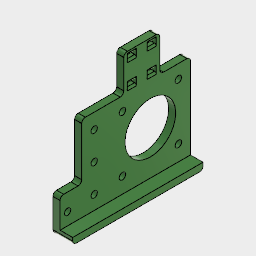
RailCore II 300ZLT (Autodesk Fusion 360 archive; units mm, degrees)
design "Titan_Mount"
Autodesk Fusion 360 part; units mm, degrees
(part 1 of 2)
sketch "sketch 380" plane through (7.7978, 0, 0) normal (-1, 0, 0) x (0, 0, 1)
  circle A0 centre (-23.4476, 32.6221) radius 1.75
  circle A1 centre (8.4572, 79.2609) radius 1.8
  circle A2 centre (-22.5428, 48.2609) radius 1.8
  circle A3 centre (-22.5428, 79.2609) radius 1.8
  circle A4 centre (8.4572, 48.2609) radius 1.8
  circle A5 centre (-7.0428, 63.7609) radius 14
  circle A6 centre (-7.9476, 32.6221) radius 1.75
  circle A7 centre (7.5524, 32.6221) radius 1.75
  line L0 (16, 25.672) -> (-34.9535, 25.672)
  line L1 (16, 86) -> (16, 25.672)
  line L2 (-34.9535, 86) -> (16, 86)
  line L3 (-34.9535, 25.672) -> (-34.9535, 86)
extrude "Extrude1" add sketch "sketch 380" along normal blind 4
sketch "sketch 426" plane through (7.7978, 0, 0) normal (1, 0, 0) x (0, 0, -1)
  line L0 (34.9535, 25.672) -> (34.9535, 86)
  line L1 (34.9535, 25.672) -> (34.9535, 86)
  line L2 (34.9535, 86) -> (31.2032, 86)
  line L3 (34.9535, 86) -> (31.2032, 86)
  line L4 (31.2032, 86) -> (31.2032, 25.672)
  line L5 (31.2032, 25.672) -> (34.9535, 25.672)
  line L6 (31.2032, 25.672) -> (34.9535, 25.672)
extrude "Extrude2" add sketch "sketch 426" along normal blind 7
sketch "Sketch1" plane through (0, 0, 16) normal (0, 0, 1) x (-1, 0, 0)
  line L0 (-7.7978, -25.672) -> (-7.7978, -86)
  line L1 (-3.7978, -86) -> (-3.7978, -25.672)
  line L2 (-3.7978, -69) -> (-7.7982, -69)
  line L3 (-7.7978, -49) -> (-3.7968, -49)
  line L4 (-7.7978, -86) -> (-3.7978, -86)
  line L5 (-3.7978, -25.672) -> (-7.7978, -25.672)
  dimension "d1" = 20
  measures "d1" distance of L2 L3
extrude "Extrude3" add sketch "Sketch1" along normal blind 20 contours L0 L1 L2 L3
sketch "Sketch2" plane through (7.7978, 0, 0) normal (1, 0, 0) x (0, 1, 0)
  line L0 (25.672, 16) -> (25.672, -31.2032)
  line L1 (25.672, -31.2032) -> (86, -31.2032)
  line L2 (86, -31.2032) -> (86, 16)
  line L3 (86, 16) -> (69, 16)
  line L4 (69, 16) -> (69, 36)
  line L5 (69, 36) -> (49, 36)
  line L6 (49, 36) -> (49, 16)
  line L7 (49, 16) -> (25.672, 16)
  circle A0 centre (32.6221, -7.9476) radius 1.75
  circle A1 centre (32.6221, 7.5524) radius 1.75
  circle A2 centre (63.7609, -7.0428) radius 14
  circle A3 centre (48.2609, 8.4572) radius 1.8
  circle A4 centre (79.2609, -22.5428) radius 1.8
  circle A5 centre (48.2609, -22.5428) radius 1.8
  circle A6 centre (79.2609, 8.4572) radius 1.8
  circle A7 centre (32.6221, -23.4476) radius 1.75
  line L8 (67, 34) -> (62, 34)
  line L9 (62, 34) -> (62, 31.5)
  line L10 (62, 31.5) -> (67, 31.5)
  line L11 (67, 31.5) -> (67, 34)
  line L12 (51, 34) -> (56, 34)
  line L13 (56, 34) -> (56, 31.5)
  line L14 (56, 31.5) -> (51, 31.5)
  line L15 (51, 31.5) -> (51, 34)
  line L16 (51, 20.5) -> (56, 20.5)
  line L17 (56, 20.5) -> (56, 18)
  line L18 (56, 18) -> (51, 18)
  line L19 (51, 18) -> (51, 20.5)
  line L20 (62, 20.5) -> (67, 20.5)
  line L21 (67, 20.5) -> (67, 18)
  line L22 (67, 18) -> (62, 18)
  line L23 (62, 18) -> (62, 20.5)
  dimension "d5" = 5
  dimension "d6" = 2.5
  dimension "d7" = 5
  dimension "d8" = 2.5
  dimension "d9" = 2.5
  dimension "d10" = 5
  dimension "d11" = 5
  dimension "d12" = 2.5
  dimension "d13" = 2
  dimension "d14" = 2
  dimension "d15" = 2
  dimension "d16" = 2
  dimension "d17" = 2
  dimension "d18" = 2
  dimension "d19" = 11
  dimension "d20" = 11
  measures "d5" distance of L8.start L8.end
  measures "d6" distance of L8.start L10.end
  measures "d7" distance of L12.start L12.end
  measures "d8" distance of L12.start L14.end
  measures "d9" distance of L16.start L18.end
  measures "d10" distance of L16.start L16.end
  measures "d11" distance of L20.start L20.end
  measures "d12" distance of L20.start L22.end
  measures "d13" distance of L6 L15
  measures "d14" distance of L6 L19
  measures "d15" distance of L4 L21
  measures "d16" distance of L4 L11
  measures "d17" distance of L5 L12
  measures "d18" distance of L5 L8
  measures "d19" distance of L14 L16
  measures "d20" distance of L10 L20
extrude "Extrude4" cut sketch "Sketch2" against normal up to surface (4 mm away) contours L8 L9 L10 L11 | L12 L13 L14 L15 | L16 L17 L18 L19 | L20 L21 L22 L23
fillet "Fillet3" radius 2 4 edges at (5.7978, 49, 16) (5.7978, 49, 36) (5.7978, 69, 16) (5.7978, 69, 36)
fillet "Fillet4" radius 1 16 edges at (3.7978, 64.5, 18) (3.7978, 64.5, 20.5) (3.7978, 64.5, 31.5) (3.7978, 64.5, 34) (3.7978, 53.5, 34) (3.7978, 53.5, 31.5) (3.7978, 53.5, 20.5) (3.7978, 53.5, 18) (7.7978, 64.5, 18) (7.7978, 53.5, 18) (7.7978, 53.5, 20.5) (7.7978, 64.5, 20.5) (7.7978, 64.5, 31.5) (7.7978, 53.5, 31.5) (7.7978, 53.5, 34) (7.7978, 64.5, 34)
sketch "Sketch3" plane through (0, 25.672, 0) normal (0, -1, 0) x (1, 0, 0)
  line L0 (3.7978, 16) -> (3.7978, -34.9535)
  line L1 (3.7978, -34.9535) -> (14.7978, -34.9535)
  line L2 (14.7978, -31.2032) -> (7.7978, -31.2032)
  line L3 (7.7978, -31.2032) -> (7.7978, 16)
  line L4 (7.7978, -14.9535) -> (3.7978, -14.9535)
  line L5 (14.7978, -34.9535) -> (14.7978, -31.2032)
  line L6 (7.7978, 16) -> (3.7978, 16)
  dimension "d25" = 20
  measures "d25" distance of L1 L4
extrude "Extrude5" add sketch "Sketch3" along normal blind 12 contours L0 L1 L2 L3 L4 L5
fillet "Fillet5" radius 2 7 edges at (3.7978, 49.836, -34.9535) (9.2978, 86, -34.9535) (5.7978, 86, 16) (5.7978, 25.672, 16) (5.7978, 25.672, -14.9535) (5.7978, 13.672, -14.9535) (9.2978, 13.672, -34.9535)
sketch "Sketch4" plane through (3.7978, 0, 0) normal (-1, 0, 0) x (0, -1, 0)
  circle A0 centre (-32.6221, -23.4476) radius 1.75
  circle A1 centre (-79.2609, 8.4572) radius 1.8
  circle A2 centre (-48.2609, -22.5428) radius 1.8
  circle A3 centre (-79.2609, -22.5428) radius 1.8
  circle A4 centre (-48.2609, 8.4572) radius 1.8
  circle A5 centre (-63.7609, -7.0428) radius 14
  circle A6 centre (-32.6221, 7.5524) radius 1.75
  circle A7 centre (-32.6221, -7.9476) radius 1.75
  line L0 (-62, 21.5) -> (-62, 17)
  line L1 (-62, 17) -> (-67, 17)
  line L2 (-67, 17) -> (-67, 21.5)
  line L3 (-67, 21.5) -> (-62, 21.5)
  line L4 (-62, 35) -> (-62, 30.5)
  line L5 (-62, 30.5) -> (-67, 30.5)
  line L6 (-67, 30.5) -> (-67, 35)
  line L7 (-67, 35) -> (-62, 35)
  line L8 (-56, 30.5) -> (-56, 35)
  line L9 (-56, 35) -> (-51, 35)
  line L10 (-51, 35) -> (-51, 30.5)
  line L11 (-51, 30.5) -> (-56, 30.5)
  line L12 (-56, 17) -> (-56, 21.5)
  line L13 (-56, 21.5) -> (-51, 21.5)
  line L14 (-51, 21.5) -> (-51, 17)
  line L15 (-51, 17) -> (-56, 17)
  arc A8 (-13.672, -16.9535) -> (-15.672, -14.9535) centre (-15.672, -16.9535) ccw
  line L16 (-15.672, -14.9535) -> (-23.672, -14.9535)
  arc A9 (-25.672, -12.9535) -> (-23.672, -14.9535) centre (-23.672, -12.9535) ccw
  line L17 (-25.672, -12.9535) -> (-25.672, 14)
  arc A10 (-25.672, 14) -> (-27.672, 16) centre (-27.672, 14) ccw
  line L18 (-27.672, 16) -> (-47, 16)
  arc A11 (-49, 18) -> (-47, 16) centre (-47, 18) ccw
  line L19 (-49, 18) -> (-49, 34)
  arc A12 (-49, 34) -> (-51, 36) centre (-51, 34) ccw
  line L20 (-51, 36) -> (-67, 36)
  arc A13 (-67, 36) -> (-69, 34) centre (-67, 34) ccw
  line L21 (-69, 34) -> (-69, 18)
  arc A14 (-71, 16) -> (-69, 18) centre (-71, 18) ccw
  line L22 (-71, 16) -> (-84, 16)
  arc A15 (-84, 16) -> (-86, 14) centre (-84, 14) ccw
  line L23 (-86, 14) -> (-86, -32.9535)
  line L24 (-86, -32.9535) -> (-13.672, -32.9535)
  line L25 (-13.672, -32.9535) -> (-13.672, -16.9535)
  line L26 (-32.6221, -23.4476) -> (-17.8531, -23.4476) construction
  line L27 (-17.8531, -23.4476) -> (-17.8531, -24.4346) construction
  line L28 (-17.8531, -24.4346) -> (-32.6221, -24.4346) construction
  line L29 (-32.6221, -24.4346) -> (-32.6221, -23.4476) construction
  circle A16 centre (-17.8531, -24.4346) radius 1.75
  dimension "d30" = 0.987
  dimension "d31" = 14.769
  dimension "d32" = 3.5
  measures "d30" distance of L26 L28
  measures "d31" distance of L27 L29
  measures "d32" diameter of A16
extrude "Extrude6" cut sketch "Sketch4" against normal up to surface (4 mm away) contours A16

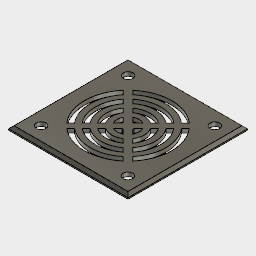
design "Fan_Cover"
Autodesk Fusion 360 part; units mm, degrees
sketch "Sketch1" plane through (0, 0, 0) normal (0, 0, 1) x (1, 0, 0)
  circle A0 centre (1.9885, 1.9886) radius 1.75
  circle A1 centre (2.0234, 33.9886) radius 1.75
  circle A2 centre (34.0234, 33.9537) radius 1.75
  circle A3 centre (33.9885, 1.9537) radius 1.75
  line L0 (-4.0115, 39.9886) -> (39.9885, 39.9886)
  line L1 (39.9885, 39.9886) -> (39.9885, -4.0114)
  line L2 (39.9885, -4.0114) -> (-4.0115, -4.0114)
  line L3 (-4.0115, -4.0114) -> (-4.0115, 39.9886)
  circle A4 centre (18, 18) radius 2
  circle A5 centre (18, 18) radius 4
  circle A6 centre (18, 18) radius 6
  circle A7 centre (18, 18) radius 8
  circle A8 centre (18, 18) radius 10
  circle A9 centre (18, 18) radius 14
  circle A10 centre (18, 18) radius 12
  line L4 (1.9885, 1.9886) -> (34.0234, 33.9537) construction
  line L5 (2.0234, 33.9886) -> (33.9885, 1.9537) construction
  circle A11 centre (18, 18) radius 16
  line L6 (7.6057, 30.1638) -> (30.1411, 7.5792)
  line L7 (5.8378, 28.3962) -> (28.3696, 5.8152)
  line L8 (28.4273, 30.1356) -> (5.8417, 7.5992)
  line L9 (7.6103, 5.8322) -> (30.1904, 28.3632)
  line L10 (-4.0115, 17.9886) -> (39.9885, 17.9886) construction
  line L11 (17.9885, 39.9886) -> (17.9885, -4.0114) construction
  dimension "d1" = 3.5
  dimension "d2" = 3.5
  dimension "d3" = 3.5
  dimension "d4" = 3.5
  dimension "d5" = 32
  dimension "d6" = 32
  dimension "d7" = 32
  dimension "d8" = 32
  dimension "d14" = 6
  dimension "d15" = 6
  dimension "d16" = 6
  dimension "d17" = 6
  dimension "d18" = 4
  dimension "d30" = 8
  dimension "d31" = 12
  dimension "d32" = 16
  dimension "d33" = 20
  dimension "d34" = 28
  dimension "d35" = 24
  dimension "d41" = 32
  dimension "d42" = 1.25
  dimension "d43" = 1.25
  dimension "d44" = 1.25
  dimension "d45" = 1.25
  measures "d1" diameter of A0
  measures "d2" diameter of A1
  measures "d3" diameter of A2
  measures "d4" diameter of A3
  measures "d5" distance of A0.centre A3.centre
  measures "d6" distance of A0.centre A1.centre
  measures "d7" distance of A1.centre A2.centre
  measures "d8" distance of A2.centre A3.centre
  measures "d14" distance of A0.centre L3
  measures "d15" distance of A3.centre L1
  measures "d16" distance of A1.centre L0
  measures "d17" distance of A0.centre L2
  measures "d18" diameter of A4
  measures "d30" diameter of A5
  measures "d31" diameter of A6
  measures "d32" diameter of A7
  measures "d33" diameter of A8
  measures "d34" diameter of A9
  measures "d35" diameter of A10
  measures "d41" diameter of A11
  measures "d42" distance of L5 L7
  measures "d43" distance of L5 L6
  measures "d44" distance of L4 L8
  measures "d45" distance of L4 L9
extrude "Extrude1" add sketch "Sketch1" along normal blind 1.5 contours L0 L1 L2 L3 | A4 L6 L9 | A4 L6 L8 L9 | A4 A5 L8 L9 | A4 A5 L6 L7 | A4 L6 L7 L9 | A4 L6 L8 | L6 L7 L8 L9 | A5 A6 L6 L9 | A5 A6 L8 L9 | A4 L7 L9 | A5 A6 L6 L7 | A4 L6 L7 L8 | A4 A5 L6 L7 | A5 A6 L6 L8 | A4 L7 L8 L9 | A6 A7 L8 L9 | A4 A5 L8 L9 | A5 A6 L7 L9 | A6 A7 L6 L7 | A4 L7 L8 | A5 A6 L6 L7 | A7 A8 L6 L9 | A7 A8 L8 L9 | A5 A6 L8 L9 | A7 A8 L6 L7 | A5 A6 L7 L8 | A6 A7 L6 L7 | A7 A8 L6 L8 | A8 A10 L8 L9 | A6 A7 L8 L9 | A7 A8 L7 L9 | A8 A10 L6 L7 | A7 A8 L6 L7 | A9 A10 L6 L9 | A9 A10 L8 L9 | A7 A8 L8 L9 | A9 A10 L6 L7 | A7 A8 L7 L8 | A8 A10 L6 L7 | A9 A10 L6 L8 | A9 A11 L8 L9 | A8 A10 L8 L9 | A9 A10 L7 L9 | A9 A11 L6 L7 | A9 A10 L6 L7 | A9 A10 L8 L9 | A9 A10 L7 L8 | A9 A11 L6 L7 | A9 A11 L8 L9
chamfer "Chamfer1" distance 1 angle 45 4 edges at (17.9885, -4.0114, 1.5) (39.9885, 17.9886, 1.5) (-4.0115, 17.9886, 1.5) (17.9885, 39.9886, 1.5)

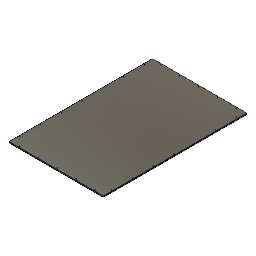
design "300ZLT Back Panel"
Autodesk Fusion 360 part; units mm, degrees
sketch "Sketch1" plane through (0, 0, 0) normal (0, 0, 1) x (1, 0, 0)
  line L0 (0, 0) -> (490, 0)
  line L1 (490, 0) -> (490, -745)
  line L2 (490, -745) -> (0, -745)
  line L3 (0, -745) -> (0, 0)
  line L4 (7.5, -7.5) -> (482.5, -7.5) construction
  line L5 (482.5, -7.5) -> (482.5, -737.5) construction
  line L6 (482.5, -737.5) -> (7.5, -737.5) construction
  line L7 (7.5, -737.5) -> (7.5, -7.5) construction
  line L8 (0, -50) -> (490, -50) construction
  line L9 (0, -695) -> (490, -695) construction
  line L10 (0, -157.5) -> (490, -157.5) construction
  line L11 (0, -265) -> (490, -265) construction
  line L12 (0, -372.5) -> (490, -372.5) construction
  line L13 (50, 0) -> (50, -745) construction
  line L14 (440, 0) -> (440, -745) construction
  line L15 (147.5, 0) -> (147.5, -745) construction
  line L16 (245, 0) -> (245, -745) construction
  line L17 (342.5, 0) -> (342.5, -745) construction
  circle A0 centre (50, -737.5) radius 1.75
  circle A1 centre (147.5, -737.5) radius 1.75
  circle A2 centre (245, -737.5) radius 1.75
  circle A3 centre (342.5, -737.5) radius 1.75
  circle A4 centre (440, -737.5) radius 1.75
  circle A5 centre (7.5, -695) radius 1.75
  circle A6 centre (7.5, -372.5) radius 1.75
  circle A7 centre (7.5, -372.5) radius 1.75
  circle A8 centre (7.5, -157.5) radius 1.75
  circle A9 centre (7.5, -50) radius 1.75
  circle A10 centre (50, -7.5) radius 1.75
  circle A11 centre (147.5, -7.5) radius 1.75
  circle A12 centre (245, -7.5) radius 1.75
  circle A13 centre (342.5, -7.5) radius 1.75
  circle A14 centre (440, -7.5) radius 1.75
  circle A15 centre (482.5, -50) radius 1.75
  circle A16 centre (482.5, -157.5) radius 1.75
  circle A17 centre (482.5, -372.5) radius 1.75
  circle A18 centre (482.5, -372.5) radius 1.75
  circle A19 centre (482.5, -695) radius 1.75
  line L18 (0, -480) -> (490, -480) construction
  line L19 (0, -587.5) -> (490, -587.5) construction
  circle A20 centre (7.5, -480) radius 1.75
  circle A21 centre (7.5, -587.5) radius 1.75
  circle A22 centre (482.5, -480) radius 1.75
  circle A23 centre (482.5, -587.5) radius 1.75
  dimension "d1" = 745
  dimension "d2" = 490
  dimension "d3" = 7.5
  dimension "d4" = 7.5
  dimension "d5" = 7.5
  dimension "d6" = 7.5
  dimension "d9" = 50
  dimension "d10" = 50
  dimension "d11" = 107.5
  dimension "d12" = 107.5
  dimension "d13" = 107.5
  dimension "d14" = 50
  dimension "d15" = 50
  dimension "d16" = 97.5
  dimension "d17" = 97.5
  dimension "d18" = 97.5
  dimension "d20" = 3.5
  dimension "d21" = 3.5
  dimension "d22" = 3.5
  dimension "d23" = 3.5
  dimension "d24" = 3.5
  dimension "d25" = 3.5
  dimension "d26" = 3.5
  dimension "d27" = 3.5
  dimension "d28" = 3.5
  dimension "d29" = 3.5
  dimension "d30" = 3.5
  dimension "d31" = 3.5
  dimension "d32" = 3.5
  dimension "d33" = 3.5
  dimension "d34" = 3.5
  dimension "d35" = 3.5
  dimension "d36" = 3.5
  dimension "d37" = 3.5
  dimension "d38" = 3.5
  dimension "d39" = 3.5
  dimension "d50" = 107.5
  dimension "d51" = 107.5
  dimension "d52" = 3.5
  dimension "d53" = 3.5
  dimension "d54" = 3.5
  dimension "d55" = 3.5
  measures "d1" distance of L0.start L2.end
  measures "d2" distance of L0.start L0.end
  measures "d3" distance of L3 L7
  measures "d4" distance of L2 L6
  measures "d5" distance of L0 L4
  measures "d6" distance of L1 L5
  measures "d9" distance of L0 L8
  measures "d10" distance of L2 L9
  measures "d11" distance of L8 L10
  measures "d12" distance of L10 L11
  measures "d13" distance of L11 L12
  measures "d14" distance of L3 L13
  measures "d15" distance of L1 L14
  measures "d16" distance of L13 L15
  measures "d17" distance of L15 L16
  measures "d18" distance of L16 L17
  measures "d20" diameter of A0
  measures "d21" diameter of A1
  measures "d22" diameter of A2
  measures "d23" diameter of A3
  measures "d24" diameter of A4
  measures "d25" diameter of A5
  measures "d26" diameter of A6
  measures "d27" diameter of A7
  measures "d28" diameter of A8
  measures "d29" diameter of A9
  measures "d30" diameter of A10
  measures "d31" diameter of A11
  measures "d32" diameter of A12
  measures "d33" diameter of A13
  measures "d34" diameter of A14
  measures "d35" diameter of A15
  measures "d36" diameter of A16
  measures "d37" diameter of A17
  measures "d38" diameter of A18
  measures "d39" diameter of A19
  measures "d50" distance of L12 L18
  measures "d51" distance of L18 L19
  measures "d52" diameter of A20
  measures "d53" diameter of A21
  measures "d54" diameter of A22
  measures "d55" diameter of A23
extrude "Extrude1" add sketch "Sketch1" along normal blind 6.35
fillet "Fillet1" radius 5 4 edges at (490, -745, 3.175) (0, -745, 3.175) (0, 0, 3.175) (490, 0, 3.175)
equation "d1 = YDepth"
equation "d2 = XWidth"
equation "d3 = HoleOffset"
equation "d4 = HoleOffset"
equation "d5 = HoleOffset"
equation "d6 = HoleOffset"
equation "HoleOffset = 7.5 mm"
equation "Diameter = 3.5 mm"
equation "d9 = EdgeToFirstHole"
equation "d10 = EdgeToFirstHole"
equation "d11 = YSpacing"
equation "d12 = YSpacing"
equation "d13 = YSpacing"
equation "d14 = EdgeToFirstHole"
equation "d15 = EdgeToFirstHole"
equation "d16 = XSpacing"
equation "d17 = XSpacing"
equation "d18 = XSpacing"
equation "d20 = Diameter"
equation "d21 = Diameter"
equation "d22 = Diameter"
equation "d23 = Diameter"
equation "d24 = Diameter"
equation "d25 = Diameter"
equation "d26 = Diameter"
equation "d27 = Diameter"
equation "d28 = Diameter"
equation "d29 = Diameter"
equation "d30 = Diameter"
equation "d31 = Diameter"
equation "d32 = Diameter"
equation "d33 = Diameter"
equation "d34 = Diameter"
equation "d35 = Diameter"
equation "d36 = Diameter"
equation "d37 = Diameter"
equation "d38 = Diameter"
equation "d39 = Diameter"
equation "EdgeToFirstHole = 50 mm"
equation "YDepth = 745 mm"
equation "XWidth = 490 mm"
equation "YSpacing = ( YDepth - ( 2 * EdgeToFirstHole ) ) / 6"
equation "XSpacing = ( XWidth - ( 2 * EdgeToFirstHole ) ) / 4"
equation "thickness = 0.25 in"
equation "d47 = thickness"
equation "d50 = YSpacing"
equation "d51 = YSpacing"
equation "d52 = Diameter"
equation "d53 = Diameter"
equation "d54 = Diameter"
equation "d55 = Diameter"

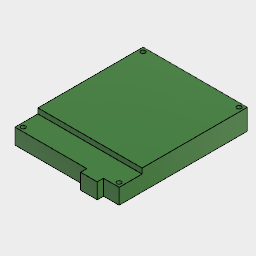
design "DuetWifi v2"
Autodesk Fusion 360 part; units mm, degrees
sketch "Sketch1" plane through (0, 0, 0) normal (0, 0, 1) x (1, 0, 0)
  line L0 (0, 0) -> (100, 0)
  line L1 (100, 0) -> (100, -123)
  line L2 (100, -123) -> (0, -123)
  line L3 (0, -123) -> (0, 0)
  line L4 (85, -123) -> (69, -123)
  line L5 (69, -123) -> (69, -129)
  line L6 (69, -129) -> (85, -129)
  line L7 (85, -129) -> (85, -123)
  circle A0 centre (4, -119) radius 2.1
  circle A1 centre (96, -119) radius 2.1
  circle A2 centre (4, -4) radius 2.1
  circle A3 centre (96, -4) radius 2.1
  line L8 (0, -101) -> (100, -101)
  dimension "d1" = 100
  dimension "d2" = 123
  dimension "d3" = 16
  dimension "d4" = 6
  dimension "d5" = 15
  dimension "d6" = 4.2
  dimension "d7" = 4.2
  dimension "d8" = 4.2
  dimension "d9" = 4.2
  dimension "d10" = 4
  dimension "d11" = 4
  dimension "d12" = 4
  dimension "d13" = 4
  dimension "d14" = 4
  dimension "d15" = 4
  dimension "d16" = 4
  dimension "d17" = 4
  dimension "d18" = 22
  measures "d1" distance of L0.start L0.end
  measures "d2" distance of L0.start L2.end
  measures "d3" distance of L4.start L4.end
  measures "d4" distance of L4.start L6.end
  measures "d5" distance of L1 L7
  measures "d6" diameter of A0
  measures "d7" diameter of A1
  measures "d8" diameter of A2
  measures "d9" diameter of A3
  measures "d10" distance of L3 A2.centre
  measures "d11" distance of L0 A2.centre
  measures "d12" distance of L0 A3.centre
  measures "d13" distance of L1 A3.centre
  measures "d14" distance of L2 A0.centre
  measures "d15" distance of L3 A0.centre
  measures "d16" distance of L2 A1.centre
  measures "d17" distance of L1 A1.centre
  measures "d18" distance of L2 L8
extrude "Extrude1" add sketch "Sketch1" along normal blind 15 contours L1 L2 L3 L4 L8 | L2 L4 L5 L6 L7
extrude "Extrude2" add sketch "Sketch1" along normal blind 20 contours L0 L1 L3 L8

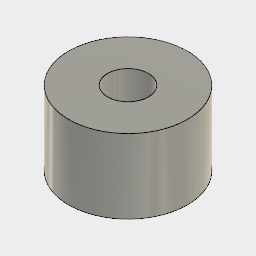
design "Idler_Spacer"
Autodesk Fusion 360 part; units mm, degrees
sketch "Sketch1" plane through (0, 0, 0) normal (0, 0, 1) x (1, 0, 0)
  circle A0 centre (0, 0) radius 2.75
  circle A1 centre (0, 0) radius 8
  dimension "d1" = 5.5
  measures "d1" diameter of A0
extrude "Extrude1" add sketch "Sketch1" along normal blind 10

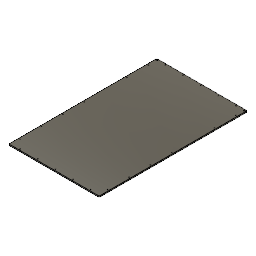
design "300ZLT Left_Panel"
Autodesk Fusion 360 part; units mm, degrees
sketch "Sketch1" plane through (0, 0, 0) normal (0, 0, 1) x (1, 0, 0)
  line L0 (0, 0) -> (455, 0)
  line L1 (455, 0) -> (455, -745)
  line L2 (455, -745) -> (0, -745)
  line L3 (0, -745) -> (0, 0)
  line L4 (7.5, -7.5) -> (447.5, -7.5) construction
  line L5 (447.5, -7.5) -> (447.5, -737.5) construction
  line L6 (447.5, -737.5) -> (7.5, -737.5) construction
  line L7 (7.5, -737.5) -> (7.5, -7.5) construction
  line L8 (0, -50) -> (455, -50) construction
  line L9 (0, -695) -> (455, -695) construction
  line L10 (0, -157.5) -> (455, -157.5) construction
  line L11 (0, -265) -> (455, -265) construction
  line L12 (0, -372.5) -> (455, -372.5) construction
  line L13 (50, 0) -> (50, -745) construction
  line L14 (405, 0) -> (405, -745) construction
  line L15 (138.75, 0) -> (138.75, -745) construction
  line L16 (227.5, 0) -> (227.5, -745) construction
  line L17 (316.25, 0) -> (316.25, -745) construction
  circle A0 centre (50, -737.5) radius 1.75
  circle A1 centre (138.75, -737.5) radius 1.75
  circle A2 centre (227.5, -737.5) radius 1.75
  circle A3 centre (316.25, -737.5) radius 1.75
  circle A4 centre (405, -737.5) radius 1.75
  circle A5 centre (7.5, -695) radius 1.75
  circle A6 centre (7.5, -372.5) radius 1.75
  circle A7 centre (7.5, -372.5) radius 1.75
  circle A8 centre (7.5, -157.5) radius 1.75
  circle A9 centre (7.5, -50) radius 1.75
  circle A10 centre (50, -7.5) radius 1.75
  circle A11 centre (138.75, -7.5) radius 1.75
  circle A12 centre (227.5, -7.5) radius 1.75
  circle A13 centre (316.25, -7.5) radius 1.75
  circle A14 centre (405, -7.5) radius 1.75
  circle A15 centre (447.5, -50) radius 1.75
  circle A16 centre (447.5, -157.5) radius 1.75
  circle A17 centre (447.5, -372.5) radius 1.75
  circle A18 centre (447.5, -372.5) radius 1.75
  circle A19 centre (447.5, -695) radius 1.75
  line L18 (0, -480) -> (455, -480) construction
  line L19 (0, -587.5) -> (455, -587.5) construction
  circle A20 centre (7.5, -480) radius 1.75
  circle A21 centre (7.5, -587.5) radius 1.75
  circle A22 centre (447.5, -587.5) radius 1.75
  circle A23 centre (447.5, -480) radius 1.75
  circle A24 centre (447.5, -7.5) radius 3.5
  circle A25 centre (7.5, -7.5) radius 3.5
  dimension "d1" = 745
  dimension "d2" = 455
  dimension "d3" = 7.5
  dimension "d4" = 7.5
  dimension "d5" = 7.5
  dimension "d6" = 7.5
  dimension "d9" = 50
  dimension "d10" = 50
  dimension "d11" = 107.5
  dimension "d12" = 107.5
  dimension "d13" = 107.5
  dimension "d14" = 50
  dimension "d15" = 50
  dimension "d16" = 88.75
  dimension "d17" = 88.75
  dimension "d18" = 88.75
  dimension "d20" = 3.5
  dimension "d21" = 3.5
  dimension "d22" = 3.5
  dimension "d23" = 3.5
  dimension "d24" = 3.5
  dimension "d25" = 3.5
  dimension "d26" = 3.5
  dimension "d27" = 3.5
  dimension "d28" = 3.5
  dimension "d29" = 3.5
  dimension "d30" = 3.5
  dimension "d31" = 3.5
  dimension "d32" = 3.5
  dimension "d33" = 3.5
  dimension "d34" = 3.5
  dimension "d35" = 3.5
  dimension "d36" = 3.5
  dimension "d37" = 3.5
  dimension "d38" = 3.5
  dimension "d39" = 3.5
  dimension "d58" = 107.5
  dimension "d59" = 107.5
  dimension "d60" = 3.5
  dimension "d61" = 3.5
  dimension "d62" = 3.5
  dimension "d63" = 3.5
  dimension "d64" = 7
  dimension "d65" = 7
  measures "d1" distance of L0.start L2.end
  measures "d2" distance of L0.start L0.end
  measures "d3" distance of L3 L7
  measures "d4" distance of L2 L6
  measures "d5" distance of L0 L4
  measures "d6" distance of L1 L5
  measures "d9" distance of L0 L8
  measures "d10" distance of L2 L9
  measures "d11" distance of L8 L10
  measures "d12" distance of L10 L11
  measures "d13" distance of L11 L12
  measures "d14" distance of L3 L13
  measures "d15" distance of L1 L14
  measures "d16" distance of L13 L15
  measures "d17" distance of L15 L16
  measures "d18" distance of L16 L17
  measures "d20" diameter of A0
  measures "d21" diameter of A1
  measures "d22" diameter of A2
  measures "d23" diameter of A3
  measures "d24" diameter of A4
  measures "d25" diameter of A5
  measures "d26" diameter of A6
  measures "d27" diameter of A7
  measures "d28" diameter of A8
  measures "d29" diameter of A9
  measures "d30" diameter of A10
  measures "d31" diameter of A11
  measures "d32" diameter of A12
  measures "d33" diameter of A13
  measures "d34" diameter of A14
  measures "d35" diameter of A15
  measures "d36" diameter of A16
  measures "d37" diameter of A17
  measures "d38" diameter of A18
  measures "d39" diameter of A19
  measures "d58" distance of L12 L18
  measures "d59" distance of L18 L19
  measures "d60" diameter of A20
  measures "d61" diameter of A21
  measures "d62" diameter of A22
  measures "d63" diameter of A23
  measures "d64" diameter of A24
  measures "d65" diameter of A25
extrude "Extrude1" add sketch "Sketch1" along normal blind 6.35
fillet "Fillet1" radius 5 4 edges at (455, -745, 3.175) (0, -745, 3.175) (0, 0, 3.175) (455, 0, 3.175)
equation "d1 = YDepth"
equation "d2 = XWidth"
equation "d3 = HoleOffset"
equation "d4 = HoleOffset"
equation "d5 = HoleOffset"
equation "d6 = HoleOffset"
equation "HoleOffset = 7.5 mm"
equation "Diameter = 3.5 mm"
equation "d9 = EdgeToFirstHole"
equation "d10 = EdgeToFirstHole"
equation "d11 = YSpacing"
equation "d12 = YSpacing"
equation "d13 = YSpacing"
equation "d14 = EdgeToFirstHole"
equation "d15 = EdgeToFirstHole"
equation "d16 = XSpacing"
equation "d17 = XSpacing"
equation "d18 = XSpacing"
equation "d20 = Diameter"
equation "d21 = Diameter"
equation "d22 = Diameter"
equation "d23 = Diameter"
equation "d24 = Diameter"
equation "d25 = Diameter"
equation "d26 = Diameter"
equation "d27 = Diameter"
equation "d28 = Diameter"
equation "d29 = Diameter"
equation "d30 = Diameter"
equation "d31 = Diameter"
equation "d32 = Diameter"
equation "d33 = Diameter"
equation "d34 = Diameter"
equation "d35 = Diameter"
equation "d36 = Diameter"
equation "d37 = Diameter"
equation "d38 = Diameter"
equation "d39 = Diameter"
equation "EdgeToFirstHole = 50 mm"
equation "YDepth = 745 mm"
equation "XWidth = 455 mm"
equation "YSpacing = ( YDepth - ( 2 * EdgeToFirstHole ) ) / 6"
equation "XSpacing = ( XWidth - ( 2 * EdgeToFirstHole ) ) / 4"
equation "thickness = 0.25 in"
equation "d47 = thickness"
equation "d58 = YSpacing"
equation "d59 = YSpacing"
equation "d60 = Diameter"
equation "d61 = Diameter"
equation "d62 = Diameter"
equation "d63 = Diameter"

design "PSU v2"
Autodesk Fusion 360 part; units mm, degrees
sketch "Sketch1" plane through (0, 0, 0) normal (0, 0, 1) x (1, 0, 0)
  line L0 (0, 0) -> (120, 0)
  line L1 (120, 0) -> (120, -220)
  line L2 (120, -220) -> (0, -220)
  line L3 (0, -220) -> (0, 0)
  line L4 (0, -15) -> (120, -15)
  line L5 (0, -205) -> (120, -205)
  circle A0 centre (12.5, -212.5) radius 3.75
  circle A1 centre (107.5, -212.5) radius 3.75
  circle A2 centre (12.5, -7.5) radius 3.75
  circle A3 centre (107.5, -7.5) radius 3.75
  dimension "d1" = 220
  dimension "d2" = 120
  dimension "d3" = 15
  dimension "d4" = 15
  dimension "d5" = 7.5
  dimension "d6" = 7.5
  dimension "d7" = 12.5
  dimension "d8" = 7.5
  dimension "d9" = 7.5
  dimension "d10" = 12.5
  dimension "d11" = 7.5
  dimension "d12" = 7.5
  dimension "d13" = 12.5
  dimension "d14" = 7.5
  dimension "d15" = 12.5
  dimension "d16" = 7.5
  measures "d1" distance of L0.start L2.end
  measures "d2" distance of L0.start L0.end
  measures "d3" distance of L0 L4
  measures "d4" distance of L2 L5
  measures "d5" diameter of A0
  measures "d6" diameter of A1
  measures "d7" distance of L3 A0.centre
  measures "d8" distance of L2 A0.centre
  measures "d9" distance of L2 A1.centre
  measures "d10" distance of L1 A1.centre
  measures "d11" diameter of A2
  measures "d12" diameter of A3
  measures "d13" distance of L3 A2.centre
  measures "d14" distance of L0 A2.centre
  measures "d15" distance of L1 A3.centre
  measures "d16" distance of L0 A3.centre
extrude "Extrude1" add sketch "Sketch1" along normal blind 2 contours L0 L1 L3 L4 | L1 L2 L3 L5 makes body 1 at (2.9167, -7.5, 0) makes body 2 at (117.0833, -212.5, 0)
extrude "Extrude2" add sketch "Sketch1" along normal blind 55 contours L1 L3 L4 L5 bodies 1 2

design "300ZL Bed"
Autodesk Fusion 360 part; units mm, degrees
sketch "Sketch1" plane through (0, 0, 0) normal (0, 0, 1) x (1, 0, 0)
  line L0 (0, 0) -> (366, 0)
  line L1 (366, 0) -> (366, 325)
  line L2 (366, 325) -> (0, 325)
  line L3 (0, 325) -> (0, 0)
  circle A0 centre (9, 290) radius 1.7
  circle A1 centre (9, 35) radius 1.7
  line L4 (9, 291.7) -> (0, 291.7)
  line L5 (9, 288.3) -> (0, 288.3)
  line L6 (9, 36.7) -> (0, 36.7)
  line L7 (9, 33.3) -> (0, 33.3)
  circle A2 centre (357, 162.5) radius 1.7
  line L8 (357, 164.2) -> (366, 164.2)
  line L9 (357, 160.8) -> (366, 160.8)
  line L10 (0, 278.3) -> (12.5, 278.3)
  line L11 (12.5, 278.3) -> (12.5, 46.7)
  line L12 (12.5, 46.7) -> (0, 46.7)
  line L13 (0, 46.7) -> (0, 278.3)
  line L14 (0, 325) -> (12.5, 325)
  line L15 (12.5, 325) -> (12.5, 301.7)
  line L16 (12.5, 301.7) -> (0, 301.7)
  line L17 (0, 301.7) -> (0, 325)
  line L18 (0, 23.3) -> (12.5, 23.3)
  line L19 (12.5, 23.3) -> (12.5, 0)
  line L20 (12.5, 0) -> (0, 0)
  line L21 (0, 0) -> (0, 23.3)
  line L22 (366, 325) -> (353.5, 325)
  line L23 (353.5, 325) -> (353.5, 174.2)
  line L24 (353.5, 174.2) -> (366, 174.2)
  line L25 (366, 174.2) -> (366, 325)
  line L26 (366, 0) -> (353.5, 0)
  line L27 (353.5, 0) -> (353.5, 150.8)
  line L28 (353.5, 150.8) -> (366, 150.8)
  line L29 (366, 150.8) -> (366, 0)
  circle A3 centre (357, 162.5) radius 5
  line L30 (356.9863, 157.5) -> (366, 157.4753)
  line L31 (357, 167.5) -> (366, 167.5)
  circle A4 centre (9, 35) radius 5
  line L32 (9, 30) -> (0, 30)
  line L33 (9, 40) -> (0, 40)
  circle A5 centre (9, 290) radius 5
  line L34 (0, 285) -> (9, 285)
  line L35 (0, 295) -> (9, 295)
  dimension "d1" = 366
  dimension "d2" = 325
  dimension "d3" = 3.4
  dimension "d4" = 3.4
  dimension "d5" = 9
  dimension "d6" = 9
  dimension "d8" = 35
  dimension "d9" = 255
  dimension "d10" = 3.4
  dimension "d11" = 9
  dimension "d12" = 162.5
  dimension "d15" = 10
  dimension "d16" = 10
  dimension "d17" = 10
  dimension "d18" = 10
  dimension "d19" = 12.5
  dimension "d20" = 12.5
  dimension "d21" = 12.5
  dimension "d22" = 12.5
  dimension "d23" = 12.5
  dimension "d24" = 10
  dimension "d25" = 10
  dimension "d40" = 10
  dimension "d41" = 10
  dimension "d42" = 10
  measures "d1" distance of L0.start L0.end
  measures "d2" distance of L0.start L2.end
  measures "d3" diameter of A0
  measures "d4" diameter of A1
  measures "d5" distance of L3 A1.centre
  measures "d6" distance of L3 A0.centre
  measures "d8" distance of L2 A0.centre
  measures "d9" distance of A0.centre A1.centre
  measures "d10" diameter of A2
  measures "d11" distance of L1 A2.centre
  measures "d12" distance of L2 A2.centre
  measures "d15" distance of L6 L12
  measures "d16" distance of L5 L10
  measures "d17" distance of L4 L16
  measures "d18" distance of L7 L18
  measures "d19" distance of L11 L13
  measures "d20" distance of L3 L19
  measures "d21" distance of L3 L15
  measures "d22" distance of L27 L29
  measures "d23" distance of L1 L23
  measures "d24" distance of L8 L24
  measures "d25" distance of L9 L28
  measures "d40" diameter of A3
  measures "d41" diameter of A4
  measures "d42" diameter of A5
extrude "Extrude1" add sketch "Sketch1" along normal blind 6.35 contours L0 L1 L2 L3 L10 L11 L12 L15 L16 L18 L19 L23 L24 L27 L28 A3 L30 L31 A4 L32 L33 A5 L34 L35
extrude "Extrude3" add sketch "Sketch1" along normal blind 3.35 contours L3 L7 A4 L32 | A1 L6 L7 A4 | L3 L6 A4 L33 | L1 L9 A3 L30 | A2 L8 L9 A3 | L1 L8 A3 L31 | L3 L5 A5 L34 | A0 L4 L5 A5 | L3 L4 A5 L35 picked at (12.8098, 35.7874) picked at (356.6583, 158.6256) picked at (9.2372, 286.117)
fillet "Fillet1" radius 7.5 4 edges at (12.5, 0, 3.175) (353.5, 0, 3.175) (353.5, 325, 3.175) (12.5, 325, 3.175)
fillet "Fillet2" radius 7.5 6 edges at (0, 278.3, 3.175) (0, 301.7, 3.175) (0, 23.3, 3.175) (0, 46.7, 3.175) (366, 150.8, 3.175) (366, 174.2, 3.175)
sketch "Sketch2" plane through (0, 0, 6.35) normal (0, 0, 1) x (-1, 0, 0)
  arc A0 (-365.9572, -167.5) -> (-358.5, -174.2) centre (-358.5, -166.7) ccw
  line L0 (-358.5, -174.2) -> (-353.5, -174.2)
  line L1 (-353.5, -174.2) -> (-353.5, -317.5)
  arc A1 (-353.5, -317.5) -> (-346, -325) centre (-346, -317.5) ccw
  line L2 (-346, -325) -> (-20, -325)
  arc A2 (-20, -325) -> (-12.5, -317.5) centre (-20, -317.5) ccw
  line L3 (-12.5, -317.5) -> (-12.5, -301.7)
  line L4 (-12.5, -301.7) -> (-7.5, -301.7)
  arc A3 (-7.5, -301.7) -> (-0.0428, -295) centre (-7.5, -294.2) ccw
  line L5 (-7.5, -278.3) -> (-12.5, -278.3)
  line L6 (-12.5, -278.3) -> (-12.5, -46.7)
  line L7 (-12.5, -46.7) -> (-7.5, -46.7)
  line L8 (-7.5, -23.3) -> (-12.5, -23.3)
  line L9 (-12.5, -23.3) -> (-12.5, -7.5)
  arc A4 (-12.5, -7.5) -> (-20, 0) centre (-20, -7.5) ccw
  line L10 (-20, 0) -> (-346, 0)
  arc A5 (-346, 0) -> (-353.5, -7.5) centre (-346, -7.5) ccw
  line L11 (-353.5, -7.5) -> (-353.5, -150.8)
  line L12 (-353.5, -150.8) -> (-358.5, -150.8)
  line L13 (-18, -312.5) -> (-318, -312.5) construction
  line L14 (-318, -312.5) -> (-318, -12.5) construction
  line L15 (-318, -12.5) -> (-18, -12.5) construction
  line L16 (-18, -12.5) -> (-18, -312.5) construction
  circle A6 centre (-168, -144.3) radius 1.5
  line L17 (-168, -142.8) -> (-353.5, -142.8)
  line L18 (-168, -145.8) -> (-353.5, -145.8)
  line L19 (-168, -312.5) -> (-168, -12.5) construction
  line L20 (-318, -162.5) -> (-18, -162.5) construction
  line L21 (-365.9545, -157.4754) -> (-356.9863, -157.5)
  arc A7 (-357, -167.5) -> (-356.9863, -157.5) centre (-357, -162.5) ccw
  line L22 (-357, -167.5) -> (-365.9572, -167.5)
  line L23 (-0.0428, -295) -> (-9, -295)
  arc A8 (-9, -285) -> (-9, -295) centre (-9, -290) ccw
  line L24 (-9, -285) -> (-0.0428, -285)
  line L25 (-0.0428, -40) -> (-9, -40)
  arc A9 (-9, -30) -> (-9, -40) centre (-9, -35) ccw
  line L26 (-9, -30) -> (-0.0428, -30)
  arc A10 (-0.0428, -285) -> (-7.5, -278.3) centre (-7.5, -285.8) ccw
  arc A11 (-7.5, -46.7) -> (-0.0428, -40) centre (-7.5, -39.2) ccw
  arc A12 (-0.0428, -30) -> (-7.5, -23.3) centre (-7.5, -30.8) ccw
  arc A13 (-358.5, -150.8) -> (-365.9545, -157.4754) centre (-358.5, -158.3) ccw
  point P0 (-168, -165.7)
  dimension "d28" = 300
  dimension "d29" = 300
  dimension "d30" = 12.5
  dimension "d31" = 5.5
  dimension "d32" = 3
  dimension "d39" = 5
  measures "d28" distance of L13.start L13.end
  measures "d29" distance of L13.start L15.end
  measures "d30" distance of L2 L13
  measures "d31" distance of L6 L16
  measures "d32" diameter of A6
  measures "d39" distance of L11.end L18.end
extrude "Extrude2" cut sketch "Sketch2" against normal blind 2.5 contours L11 A6 L17 L18 | A6
fillet "Fillet3" radius 5 6 edges at (353.5, 174.2, 3.175) (353.5, 150.8, 3.175) (12.5, 23.3, 3.175) (12.5, 46.7, 3.175) (12.5, 278.3, 3.175) (12.5, 301.7, 3.175)
equation "d8 = ( d2 - d9 ) / 2"
equation "d12 = d2 / 2"
equation "d20 = d19"
equation "d21 = d19"
equation "d22 = d19"
equation "d23 = d19"

design "5015BlowerFan"
Autodesk Fusion 360 part; units mm, degrees
sketch "Sketch1" plane through (0, 0, 0) normal (0, 0, 1) x (1, 0, 0)
  circle A0 centre (0, 0) radius 24
  circle A1 centre (-3, -2) radius 12.5
  line L0 (23.9987, -0.2485) -> (23.9987, -27)
  line L1 (23.9987, -27) -> (3.9987, -27)
  line L2 (3.9987, -27) -> (3.9987, -23.6645)
  line L3 (0, 0) -> (25, 25) construction
  line L4 (0, 0) -> (-25, -25) construction
  circle A2 centre (20.1525, 20.1525) radius 1.75
  circle A3 centre (-20.1525, -20.1525) radius 1.75
  circle A4 centre (-20.1525, -20.1525) radius 4.5
  circle A5 centre (20.1525, 20.1525) radius 4.5
  line L5 (23.3037, 16.94) -> (19.8245, 13.5273)
  line L6 (16.8977, 23.2599) -> (13.5821, 19.787)
  line L7 (-23.3331, -16.9691) -> (-19.8503, -13.4895)
  line L8 (-17.1488, -23.5033) -> (-13.8563, -19.596)
  circle A6 centre (-3, -2) radius 17.0294
  dimension "d1" = 48
  dimension "d2" = 25
  dimension "d3" = 20
  dimension "d4" = 3.5
  dimension "d5" = 28.5
  dimension "d6" = 3.5
  dimension "d7" = 28.5
  measures "d1" diameter of A0
  measures "d2" diameter of A1
  measures "d3" distance of L0.end L1.end
  measures "d4" diameter of A2
  measures "d5" distance of A0.centre A2.centre
  measures "d6" diameter of A3
  measures "d7" distance of A0.centre A3.centre
extrude "Extrude1" add sketch "Sketch1" against normal blind 1 contours A0 | A0 A5 L5 | A0 L0 L1 L2 | A0 A5 L6 | A5 | A0 A4 L8 | A0 A4 L7 | A4 L8 | A1 | A6 picked at (-17.4532, -22.4636)
extrude "Extrude2" add sketch "Sketch1" along normal blind 14 contours A0 | A0 A5 L5 | A0 L0 L1 L2 | A0 A5 L6 | A5 | A0 A4 L8 | A0 A4 L7 | A4 L8 picked at (-17.4532, -22.4636)
extrude "Extrude3" add sketch "Sketch1" along normal blind 13 contours A1
extrude "Extrude4" add sketch "Sketch1" along normal blind 12 contours A6
fillet "Fillet1" radius 1 2 edges at (-14.6541, -6.5202, 13) (-14.6541, -6.5202, 12)
shell "Shell1" thickness 1 removed faces 1 at (10.6654, -27, 4)

design "CornerBlock v1"
Autodesk Fusion 360 part; units mm, degrees
box "BoxPrimitive1" add length 15 width 15 height 15 placed x (0, 1, 0) y (-1, 0, 0) z (0, 0, 1) at (15, 0, 0)
hole "Hole1" at (7.5, 7.5, 15) direction (0, 0, -1) diameter 3.5 depth 15 tip angle 118 counterbore diameter 8 counterbore depth 12
hole "Hole2" at (15, 7.5, 7.5) direction (-1, 0, 0) diameter 3.5 depth 15 tip angle 118 counterbore diameter 8 counterbore depth 12
hole "Hole3" at (7.5, 15, 7.5) direction (0, -1, 0) diameter 3.5 depth 15 tip angle 118 counterbore diameter 8 counterbore depth 12

design "PSU_Vent_Cover"
Autodesk Fusion 360 part; units mm, degrees
sketch "Sketch1" plane through (0, 0, 15.4) normal (0, 0, 1) x (-1, 0, 0)
  line L0 (-30.8079, 70) -> (54.1921, 70)
  line L1 (54.1921, 70) -> (54.1921, -55)
  line L2 (54.1921, -55) -> (-30.8079, -55)
  line L3 (-30.8079, -55) -> (-30.8079, 70)
  line L4 (-134.8079, -18.4329) -> (-134.8079, -41.4329)
  arc A0 (-135.8079, -42.4329) -> (-134.8079, -41.4329) centre (-135.8079, -41.4329) ccw
  line L5 (-135.8079, -42.4329) -> (-165.8079, -42.4329)
  arc A1 (-166.8079, -41.4329) -> (-165.8079, -42.4329) centre (-165.8079, -41.4329) ccw
  line L6 (-166.8079, -41.4329) -> (-166.8079, -18.4329)
  arc A2 (-165.8079, -17.4329) -> (-166.8079, -18.4329) centre (-165.8079, -18.4329) ccw
  line L7 (-165.8079, -17.4329) -> (-135.8079, -17.4329)
  arc A3 (-134.8079, -18.4329) -> (-135.8079, -17.4329) centre (-135.8079, -18.4329) ccw
  line L8 (-134.8079, -63.4329) -> (-134.8079, -86.4329)
  arc A4 (-135.8079, -87.4329) -> (-134.8079, -86.4329) centre (-135.8079, -86.4329) ccw
  line L9 (-135.8079, -87.4329) -> (-165.8079, -87.4329)
  arc A5 (-166.8079, -86.4329) -> (-165.8079, -87.4329) centre (-165.8079, -86.4329) ccw
  line L10 (-166.8079, -86.4329) -> (-166.8079, -63.4329)
  arc A6 (-165.8079, -62.4329) -> (-166.8079, -63.4329) centre (-165.8079, -63.4329) ccw
  line L11 (-165.8079, -62.4329) -> (-135.8079, -62.4329)
  arc A7 (-134.8079, -63.4329) -> (-135.8079, -62.4329) centre (-135.8079, -63.4329) ccw
  circle A8 centre (57.1921, -58) radius 1.75
  circle A9 centre (57.1921, 73) radius 1.75
  circle A10 centre (-33.8079, -58) radius 1.75
  circle A11 centre (-33.8079, 73) radius 1.75
  line L12 (-74.8079, 82) -> (-74.8079, 130)
  line L13 (-74.8079, 130) -> (-46.8079, 130)
  line L14 (-46.8079, 130) -> (-46.8079, 82)
  line L15 (-46.8079, 82) -> (-74.8079, 82)
  circle A12 centre (-40.9579, 106.25) radius 1.75
  circle A13 centre (-80.6579, 106.25) radius 1.75
  circle A14 centre (-134.8079, -91) radius 1.75
  circle A15 centre (-166.8079, -46) radius 1.75
  circle A16 centre (-134.8079, -14) radius 1.75
  circle A17 centre (-166.8079, -59) radius 1.75
  circle A18 centre (-166.8079, -91) radius 1.75
  circle A19 centre (-134.8079, -59) radius 1.75
  circle A20 centre (-134.8079, -46) radius 1.75
  circle A21 centre (-166.8079, -14) radius 1.75
  circle A22 centre (99.1921, -130) radius 1.75
  circle A23 centre (-220.7102, -130) radius 1.75
  arc A24 (104.1921, -150) -> (119.1921, -135) centre (104.1921, -135) ccw
  line L16 (119.1921, -135) -> (119.1921, 135)
  arc A25 (119.1921, 135) -> (104.1921, 150) centre (104.1921, 135) ccw
  line L17 (104.1921, 150) -> (-225.8079, 150)
  arc A26 (-225.8079, 150) -> (-240.8079, 135) centre (-225.8079, 135) ccw
  line L18 (-240.8079, 135) -> (-240.8079, -135)
  arc A27 (-240.8079, -135) -> (-225.8079, -150) centre (-225.8079, -135) ccw
  line L19 (-225.8079, -150) -> (104.1921, -150)
  circle A28 centre (99.1921, 130) radius 1.75
  circle A29 centre (-220.8079, 130) radius 1.75
  line L20 (61.6921, -62.5) -> (-38.3079, -62.5)
  line L21 (-38.3079, -62.5) -> (-38.3079, 77.5)
  line L22 (-38.3079, 77.5) -> (61.6921, 77.5)
  line L23 (61.6921, 77.5) -> (61.6921, -62.5)
  circle A30 centre (57.1921, -58) radius 1.75
  circle A31 centre (-33.8079, -58) radius 1.75
  circle A32 centre (-33.8079, 73) radius 1.75
  circle A33 centre (57.1921, 73) radius 1.75
  line L24 (54.1921, -55) -> (54.1921, 70)
  line L25 (54.1921, 70) -> (-30.8079, 70)
  line L26 (-30.8079, 70) -> (-30.8079, -55)
  line L27 (-30.8079, -55) -> (54.1921, -55)
  dimension "d1" = 7.5
  dimension "d2" = 7.5
  dimension "d3" = 7.5
  dimension "d4" = 7.5
  measures "d1" distance of L3 L21
  measures "d2" distance of L2 L20
  measures "d3" distance of L1 L23
  measures "d4" distance of L0 L22
extrude "Extrude1" add sketch "Sketch1" along normal blind 1.5 contours L0 L1 L2 L3 L24 L25 L26 L27 | L20 L21 L22 L23
chamfer "Chamfer1" distance 1 angle 45 4 edges at (-11.6921, -77.5, 16.9) (-61.6921, -7.5, 16.9) (-11.6921, 62.5, 16.9) (38.3079, -7.5, 16.9)
sketch "Sketch2" plane through (0, 0, 16.9) normal (0, 0, 1) x (-1, 0, 0)
  circle A0 centre (57.1921, -58) radius 1.75
  circle A1 centre (-33.8079, -58) radius 1.75
  circle A2 centre (-33.8079, 73) radius 1.75
  circle A3 centre (57.1921, 73) radius 1.75
  line L0 (-37.3079, -61.5) -> (60.6921, -61.5)
  line L1 (60.6921, -61.5) -> (60.6921, 76.5)
  line L2 (60.6921, 76.5) -> (-37.3079, 76.5)
  line L3 (-37.3079, 76.5) -> (-37.3079, -61.5)
  line L4 (50.6921, -46) -> (-27.3079, -46)
  arc A4 (-27.3079, -46) -> (-27.3079, -49) centre (-27.3079, -47.5) ccw
  line L5 (-27.3079, -49) -> (50.6921, -49)
  arc A5 (50.6921, -49) -> (50.6921, -46) centre (50.6921, -47.5) ccw
  line L6 (50.6921, -47.5) -> (-27.3079, -47.5) construction
  line L7 (50.6921, -38.1429) -> (-27.3079, -38.1429)
  arc A6 (50.6921, -41.1429) -> (50.6921, -38.1429) centre (50.6921, -39.6429) ccw
  line L8 (-27.3079, -41.1429) -> (50.6921, -41.1429)
  arc A7 (-27.3079, -38.1429) -> (-27.3079, -41.1429) centre (-27.3079, -39.6429) ccw
  line L9 (50.6921, -30.2857) -> (-27.3079, -30.2857)
  arc A8 (50.6921, -33.2857) -> (50.6921, -30.2857) centre (50.6921, -31.7857) ccw
  line L10 (-27.3079, -33.2857) -> (50.6921, -33.2857)
  arc A9 (-27.3079, -30.2857) -> (-27.3079, -33.2857) centre (-27.3079, -31.7857) ccw
  line L11 (50.6921, -22.4286) -> (-27.3079, -22.4286)
  arc A10 (50.6921, -25.4286) -> (50.6921, -22.4286) centre (50.6921, -23.9286) ccw
  line L12 (-27.3079, -25.4286) -> (50.6921, -25.4286)
  arc A11 (-27.3079, -22.4286) -> (-27.3079, -25.4286) centre (-27.3079, -23.9286) ccw
  line L13 (50.6921, -14.5714) -> (-27.3079, -14.5714)
  arc A12 (50.6921, -17.5714) -> (50.6921, -14.5714) centre (50.6921, -16.0714) ccw
  line L14 (-27.3079, -17.5714) -> (50.6921, -17.5714)
  arc A13 (-27.3079, -14.5714) -> (-27.3079, -17.5714) centre (-27.3079, -16.0714) ccw
  line L15 (50.6921, -6.7143) -> (-27.3079, -6.7143)
  arc A14 (50.6921, -9.7143) -> (50.6921, -6.7143) centre (50.6921, -8.2143) ccw
  line L16 (-27.3079, -9.7143) -> (50.6921, -9.7143)
  arc A15 (-27.3079, -6.7143) -> (-27.3079, -9.7143) centre (-27.3079, -8.2143) ccw
  line L17 (50.6921, 1.1429) -> (-27.3079, 1.1429)
  arc A16 (50.6921, -1.8571) -> (50.6921, 1.1429) centre (50.6921, -0.3571) ccw
  line L18 (-27.3079, -1.8571) -> (50.6921, -1.8571)
  arc A17 (-27.3079, 1.1429) -> (-27.3079, -1.8571) centre (-27.3079, -0.3571) ccw
  line L19 (50.6921, 9) -> (-27.3079, 9)
  arc A18 (50.6921, 6) -> (50.6921, 9) centre (50.6921, 7.5) ccw
  line L20 (-27.3079, 6) -> (50.6921, 6)
  arc A19 (-27.3079, 9) -> (-27.3079, 6) centre (-27.3079, 7.5) ccw
  line L21 (50.6921, 16.8571) -> (-27.3079, 16.8571)
  arc A20 (50.6921, 13.8571) -> (50.6921, 16.8571) centre (50.6921, 15.3571) ccw
  line L22 (-27.3079, 13.8571) -> (50.6921, 13.8571)
  arc A21 (-27.3079, 16.8571) -> (-27.3079, 13.8571) centre (-27.3079, 15.3571) ccw
  line L23 (50.6921, 24.7143) -> (-27.3079, 24.7143)
  arc A22 (50.6921, 21.7143) -> (50.6921, 24.7143) centre (50.6921, 23.2143) ccw
  line L24 (-27.3079, 21.7143) -> (50.6921, 21.7143)
  arc A23 (-27.3079, 24.7143) -> (-27.3079, 21.7143) centre (-27.3079, 23.2143) ccw
  line L25 (50.6921, 32.5714) -> (-27.3079, 32.5714)
  arc A24 (50.6921, 29.5714) -> (50.6921, 32.5714) centre (50.6921, 31.0714) ccw
  line L26 (-27.3079, 29.5714) -> (50.6921, 29.5714)
  arc A25 (-27.3079, 32.5714) -> (-27.3079, 29.5714) centre (-27.3079, 31.0714) ccw
  line L27 (50.6921, 40.4286) -> (-27.3079, 40.4286)
  arc A26 (50.6921, 37.4286) -> (50.6921, 40.4286) centre (50.6921, 38.9286) ccw
  line L28 (-27.3079, 37.4286) -> (50.6921, 37.4286)
  arc A27 (-27.3079, 40.4286) -> (-27.3079, 37.4286) centre (-27.3079, 38.9286) ccw
  line L29 (50.6921, 48.2857) -> (-27.3079, 48.2857)
  arc A28 (50.6921, 45.2857) -> (50.6921, 48.2857) centre (50.6921, 46.7857) ccw
  line L30 (-27.3079, 45.2857) -> (50.6921, 45.2857)
  arc A29 (-27.3079, 48.2857) -> (-27.3079, 45.2857) centre (-27.3079, 46.7857) ccw
  line L31 (50.6921, 56.1429) -> (-27.3079, 56.1429)
  arc A30 (50.6921, 53.1429) -> (50.6921, 56.1429) centre (50.6921, 54.6429) ccw
  line L32 (-27.3079, 53.1429) -> (50.6921, 53.1429)
  arc A31 (-27.3079, 56.1429) -> (-27.3079, 53.1429) centre (-27.3079, 54.6429) ccw
  line L33 (50.6921, 64) -> (-27.3079, 64)
  arc A32 (50.6921, 61) -> (50.6921, 64) centre (50.6921, 62.5) ccw
  line L34 (-27.3079, 61) -> (50.6921, 61)
  arc A33 (-27.3079, 64) -> (-27.3079, 61) centre (-27.3079, 62.5) ccw
  dimension "d8" = 3
  dimension "d9" = 10
  dimension "d10" = 10
  dimension "d14" = 0
  dimension "d15" = 110
  dimension "d16" = 12.5
  measures "d8" diameter of A4
  measures "d9" distance of L1 A5.centre
  measures "d10" distance of L3 A4.centre
  measures "d16" distance of L0 L5
extrude "Extrude2" cut sketch "Sketch2" against normal up to surface (1.5 mm away) contours L4 A4 L5 A5 | L7 A6 L8 A7 | L9 A8 L10 A9 | L11 A10 L12 A11 | L13 A12 L14 A13 | L15 A14 L16 A15 | L17 A16 L18 A17 | L19 A18 L20 A19 | L21 A20 L22 A21 | L23 A22 L24 A23 | L25 A24 L26 A25 | L27 A26 L28 A27 | L29 A28 L30 A29 | L31 A30 L32 A31 | L33 A32 L34 A33

design "300ZLT Front Panel"
Autodesk Fusion 360 part; units mm, degrees